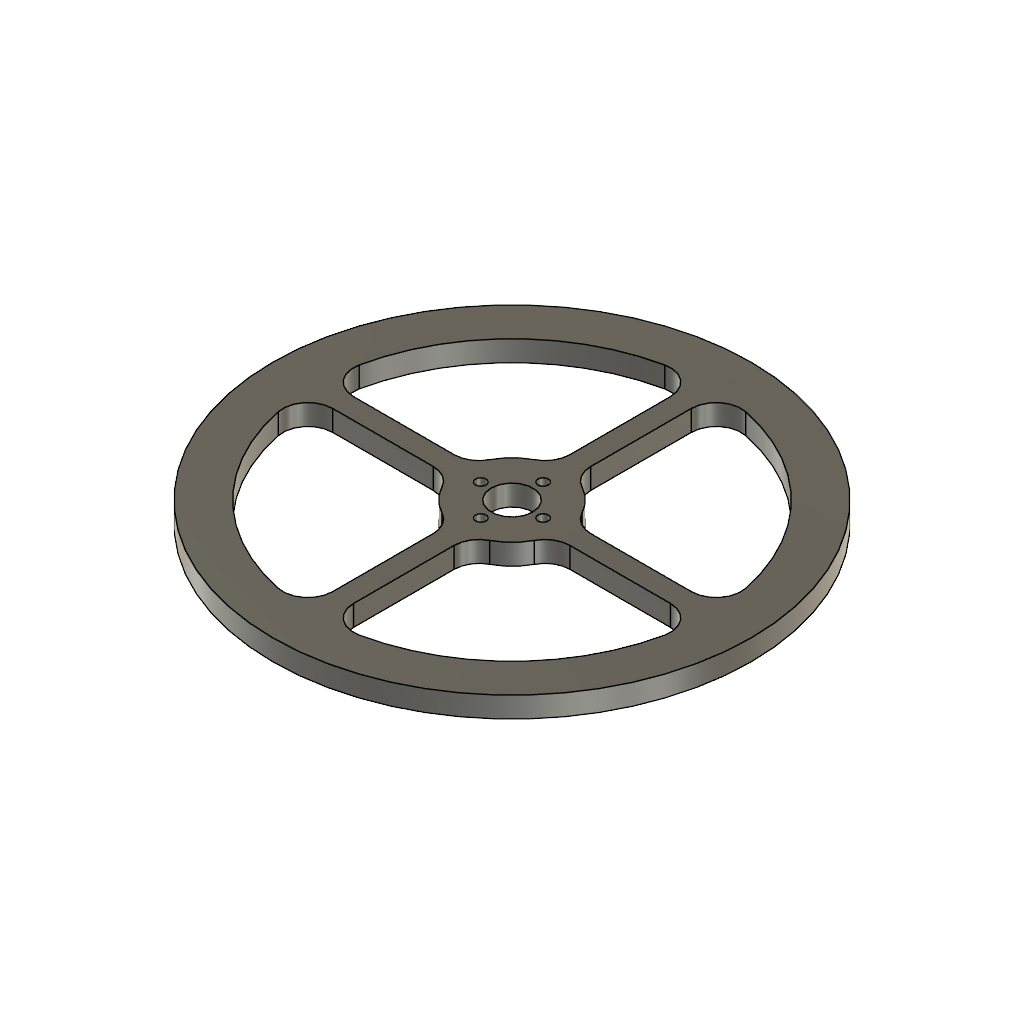
Cube_Reaction_Wheel_V2 (Autodesk Fusion 360 design; units mm, degrees)
Autodesk Fusion 360 part; units mm, degrees
sketch "Sketch1" plane through (0, 0, 0) normal (0, 0, 1) x (1, 0, 0)
  circle A0 centre (0, 0) radius 57.5
  circle A1 centre (0, 0) radius 5
  line L0 (-2.5, -40.6202) -> (-2.5, -16.4317)
  line L1 (-2.5, 16.4317) -> (-2.5, 40.6202)
  line L2 (2.5, -40.6202) -> (2.5, -16.4317)
  line L3 (2.5, 16.4317) -> (2.5, 40.6202)
  arc A2 (-9.7289, 46.493) -> (-46.493, 9.7289) centre (0, 0) ccw
  arc A3 (-46.493, -9.7289) -> (-9.7289, -46.493) centre (0, 0) ccw
  arc A4 (-5.7432, 11.1025) -> (-11.1025, 5.7432) centre (0, 0) ccw
  arc A5 (-11.1025, -5.7432) -> (-5.7432, -11.1025) centre (0, 0) ccw
  arc A6 (9.7289, -46.493) -> (46.493, -9.7289) centre (0, 0) ccw
  arc A7 (46.493, 9.7289) -> (9.7289, 46.493) centre (0, 0) ccw
  line L4 (-40.6202, 2.5) -> (-16.4317, 2.5)
  line L5 (16.4317, 2.5) -> (40.6202, 2.5)
  line L6 (-40.6202, -2.5) -> (-16.4317, -2.5)
  line L7 (16.4317, -2.5) -> (40.6202, -2.5)
  arc A8 (5.7432, -11.1025) -> (11.1025, -5.7432) centre (0, 0) ccw
  arc A9 (11.1025, 5.7432) -> (5.7432, 11.1025) centre (0, 0) ccw
  arc A10 (-46.493, 9.7289) -> (-40.6202, 2.5) centre (-40.6202, 8.5) ccw
  arc A11 (-40.6202, -2.5) -> (-46.493, -9.7289) centre (-40.6202, -8.5) ccw
  arc A12 (-2.5, 40.6202) -> (-9.7289, 46.493) centre (-8.5, 40.6202) ccw
  arc A13 (9.7289, 46.493) -> (2.5, 40.6202) centre (8.5, 40.6202) ccw
  arc A14 (40.6202, 2.5) -> (46.493, 9.7289) centre (40.6202, 8.5) ccw
  arc A15 (46.493, -9.7289) -> (40.6202, -2.5) centre (40.6202, -8.5) ccw
  arc A16 (2.5, -40.6202) -> (9.7289, -46.493) centre (8.5, -40.6202) ccw
  arc A17 (-9.7289, -46.493) -> (-2.5, -40.6202) centre (-8.5, -40.6202) ccw
  arc A18 (-11.1025, -5.7432) -> (-16.4317, -2.5) centre (-16.4317, -8.5) ccw
  arc A19 (-2.5, -16.4317) -> (-5.7432, -11.1025) centre (-8.5, -16.4317) ccw
  arc A20 (5.7432, -11.1025) -> (2.5, -16.4317) centre (8.5, -16.4317) ccw
  arc A21 (16.4317, -2.5) -> (11.1025, -5.7432) centre (16.4317, -8.5) ccw
  arc A22 (-16.4317, 2.5) -> (-11.1025, 5.7432) centre (-16.4317, 8.5) ccw
  arc A23 (-5.7432, 11.1025) -> (-2.5, 16.4317) centre (-8.5, 16.4317) ccw
  arc A24 (2.5, 16.4317) -> (5.7432, 11.1025) centre (8.5, 16.4317) ccw
  arc A25 (11.1025, 5.7432) -> (16.4317, 2.5) centre (16.4317, 8.5) ccw
  circle A26 centre (0, 7.5) radius 1.25
  circle A27 centre (-7.5, 0) radius 1.25
  circle A28 centre (0, -7.5) radius 1.25
  circle A29 centre (7.5, 0) radius 1.25
  dimension "d1" = 115
  dimension "d2" = 95
  dimension "d3" = 10
  dimension "d4" = 25
  dimension "d15" = 6
  dimension "d16" = 6
  dimension "d17" = 6
  dimension "d18" = 6
  dimension "d19" = 6
  dimension "d20" = 6
  dimension "d21" = 6
  dimension "d22" = 6
  dimension "d23" = 6
  dimension "d24" = 6
  dimension "d25" = 6
  dimension "d26" = 6
  dimension "d27" = 6
  dimension "d28" = 6
  dimension "d29" = 6
  dimension "d30" = 6
  dimension "d31" = 7.5
  dimension "d32" = 2.5
  dimension "d34" = 360
  constraint coincident A0.centre A1.centre
  constraint collinear L0 L1
  constraint collinear L2 L3
  constraint concentric A2 A7
  constraint concentric A4 A9
  constraint concentric A2 A3
  constraint concentric A4 A5
  constraint concentric A6 A7
  constraint collinear L4 L5
  constraint collinear L6 L7
  constraint concentric A8 A9
  constraint tangent L4 A10
  constraint tangent A2 A10
  constraint tangent A3 A11
  constraint tangent L6 A11
  constraint tangent A2 A12
  constraint tangent L1 A12
  constraint tangent L3 A13
  constraint tangent A7 A13
  constraint tangent L5 A14
  constraint tangent A7 A14
  constraint tangent L7 A15
  constraint tangent A6 A15
  constraint tangent L2 A16
  constraint tangent A6 A16
  constraint tangent A3 A17
  constraint tangent L0 A17
  constraint tangent L6 A18
  constraint tangent A5 A18
  constraint tangent A5 A19
  constraint tangent L0 A19
  constraint tangent L2 A20
  constraint tangent A8 A20
  constraint tangent A8 A21
  constraint tangent L7 A21
  constraint tangent L4 A22
  constraint tangent A4 A22
  constraint tangent A4 A23
  constraint tangent L1 A23
  constraint tangent A9 A24
  constraint tangent L3 A24
  constraint tangent A9 A25
  constraint tangent L5 A25
  measures "d1" diameter of A0
  measures "d2" diameter of A2
  measures "d3" diameter of A1
  measures "d4" diameter of A4
  measures "d15" radius of A10
  measures "d16" radius of A11
  measures "d17" radius of A12
  measures "d18" radius of A13
  measures "d19" radius of A14
  measures "d20" radius of A15
  measures "d21" radius of A16
  measures "d22" radius of A17
  measures "d23" radius of A18
  measures "d24" radius of A19
  measures "d25" radius of A20
  measures "d26" radius of A21
  measures "d27" radius of A22
  measures "d28" radius of A23
  measures "d29" radius of A24
  measures "d30" radius of A25
  measures "d31" distance of A0.centre A26.centre
  measures "d32" diameter of A26
extrude "Extrude1" add sketch "Sketch1" along normal blind 5
